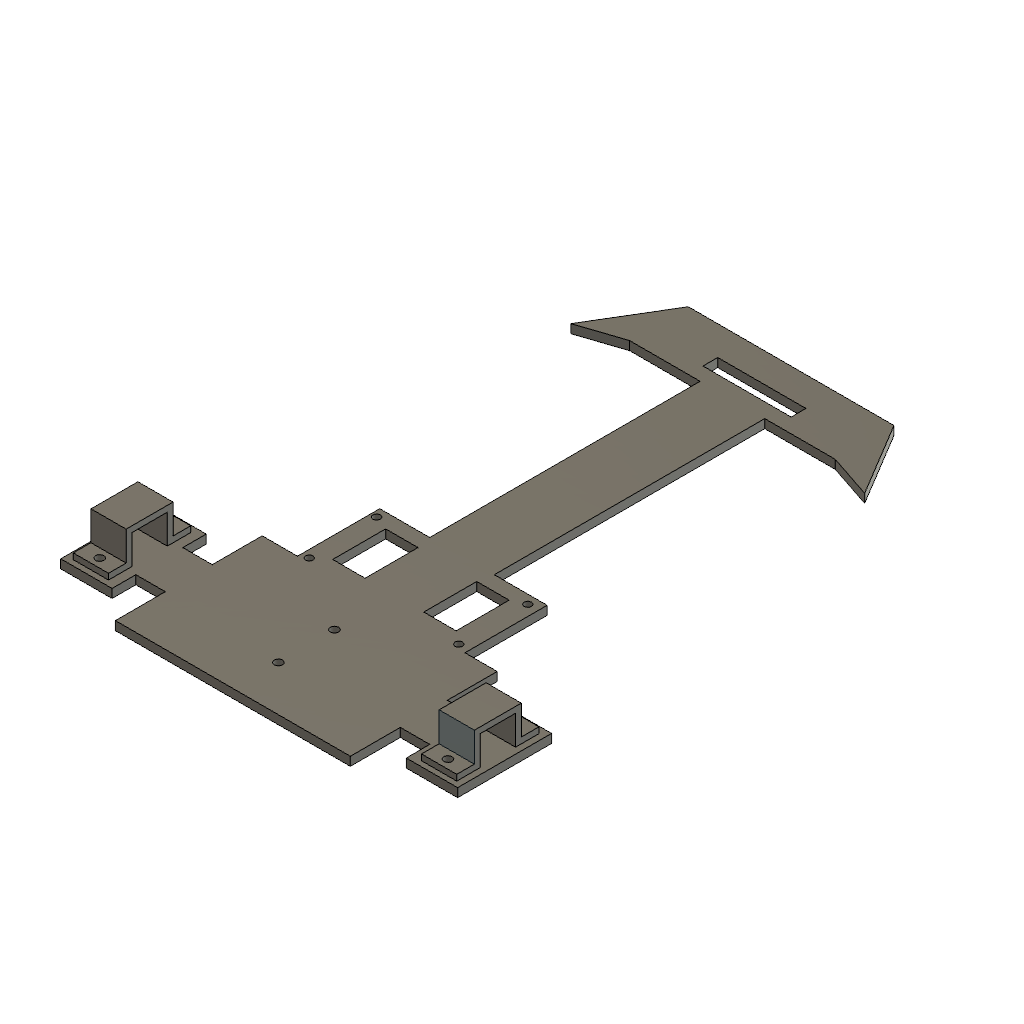
LFR (Autodesk Fusion 360 design; units mm, degrees)
part number: 2026-11-02-19-17-01-684
Autodesk Fusion 360 part; units mm, degrees
combine "Combine1" [no effect]
combine "Combine2" [no effect]
sketch "Sketch3" plane through (0, 0, 0) normal (0, 1, 0) x (1, 0, 0)
  line L0 (-67.5, 25) -> (67.5, 25)
  line L1 (67.5, 25) -> (67.5, -25)
  line L2 (67.5, -25) -> (-67.5, -25)
  line L3 (-67.5, -25) -> (-67.5, 25)
  line L4 (-10, 25) -> (10, 25)
  line L5 (10, 25) -> (10, 145)
  line L6 (10, 145) -> (-10, 145)
  line L7 (-10, 145) -> (-10, 25)
  line L8 (-35, 145) -> (35, 145)
  line L9 (35, 145) -> (35, 165)
  line L10 (35, 165) -> (-35, 165)
  line L11 (-35, 165) -> (-35, 145)
  line L12 (35, 165) -> (50, 140)
  line L13 (50, 140) -> (35, 145)
  line L14 (-35, 165) -> (-50, 140)
  line L15 (-50, 140) -> (-35, 145)
  line L16 (-15, 150) -> (15, 150)
  line L17 (15, 150) -> (15, 155)
  line L18 (15, 155) -> (-15, 155)
  line L19 (-15, 155) -> (-15, 150)
  circle A0 centre (0, 132) radius 7.5
  line L20 (-38, 20) -> (38, 20)
  line L21 (38, 20) -> (38, -20)
  line L22 (38, -20) -> (-38, -20)
  line L23 (-38, -20) -> (-38, 20)
  line L24 (-26, 53) -> (26, 53)
  line L25 (26, 53) -> (26, 25)
  line L26 (26, 25) -> (-26, 25)
  line L27 (-26, 25) -> (-26, 53)
  line L28 (-21, 30) -> (21, 30)
  line L29 (21, 30) -> (21, 48)
  line L30 (21, 48) -> (-21, 48)
  line L31 (-21, 48) -> (-21, 30)
  dimension "d11" = 135
  dimension "d12" = 50
  dimension "d13" = 20
  dimension "d14" = 120
  dimension "d15" = 70
  dimension "d16" = 20
  dimension "d17" = 15
  dimension "d18" = 76
  dimension "d19" = 40
  dimension "d20" = 52
  dimension "d21" = 28
  constraint horizontal L0
  constraint vertical L1
  constraint horizontal L2
  constraint vertical L3
  constraint horizontal L4
  constraint vertical L5
  constraint horizontal L6
  constraint vertical L7
  constraint coincident L0 L4.start
  constraint horizontal L8
  constraint vertical L9
  constraint horizontal L10
  constraint vertical L11
  constraint horizontal L16
  constraint vertical L17
  constraint horizontal L18
  constraint vertical L19
  constraint horizontal L20
  constraint vertical L21
  constraint horizontal L22
  constraint vertical L23
  constraint horizontal L24
  constraint vertical L25
  constraint horizontal L26
  constraint vertical L27
  constraint horizontal L28
  constraint vertical L29
  constraint horizontal L30
  constraint vertical L31
  measures "d11" distance of L0.start L0.end
  measures "d12" distance of L0.start L2.end
  measures "d13" distance of L4.start L4.end
  measures "d14" distance of L4.start L6.end
  measures "d15" distance of L8.start L8.end
  measures "d16" distance of L8.start L10.end
  measures "d17" diameter of A0
  measures "d18" distance of L20.start L20.end
  measures "d19" distance of L20.start L22.end
  measures "d20" distance of L24.start L24.end
  measures "d21" distance of L24.start L26.end
extrude "Extrude2" add sketch "Sketch3" along normal blind 5 contours L0 L1 L2 L3 L4 L26 | L0 L7 L24 L26 L27 L28 L30 L31 | L0 L4 L5 L7 L26 L28 | L0 L5 L24 L25 L26 L28 L29 L30 | L5 L7 L28 L30 | L5 L7 L24 L30 | L5 L6 L7 L8 L24 | L6 L8 L9 L10 L11 | L11 L14 L15 | L9 L12 L13 | L20 L21 L22 L23 makes body 1
extrude "Extrude3" cut 1 faces at (-8.6667, 5, 8.3333) along direction (0, -1, 0) blind 2 on bodies 1 bodies 1
extrude "Extrude4" add sketch "Sketch3" along normal blind 3 contours A0 bodies 1
extrude "Extrude5" add 1 faces at (26, 2, -43.6667) along direction (1, 0, 0) blind 1 on bodies 1 bodies 1
extrude "Extrude6" add 1 faces at (27, 2, -43.6667) along direction (1, 0, 0) blind 2 on bodies 1 bodies 1
extrude "Extrude7" add 1 faces at (-26, 1, -34.3333) along direction (-1, 0, 0) blind 2 on bodies 1 bodies 1
extrude "Extrude8" add 1 faces at (-10, 2, -114.3333) along direction (-1, 0, 0) blind 1 on bodies 1 bodies 1
extrude "Extrude9" add 1 faces at (10, 2, -83.6667) along direction (1, 0, 0) blind 1 on bodies 1 bodies 1
sketch "Sketch4" plane through (0, 0, 0) normal (1, 0, 0) x (0, 0, -1)
  line L0 (5, -10) -> (-7, -10)
  line L1 (-7, -10) -> (-7, -20)
  line L2 (-7, -20) -> (5, -20)
  line L3 (5, -20) -> (5, -10)
  line L4 (7, -8) -> (-9, -8)
  line L5 (-9, -8) -> (-9, -20)
  line L6 (-9, -20) -> (7, -20)
  line L7 (7, -20) -> (7, -8)
  line L8 (7, -18) -> (13, -18)
  line L9 (13, -18) -> (13, -20)
  line L10 (13, -20) -> (7, -20)
  line L11 (7, -20) -> (7, -18)
  line L12 (-9, -20) -> (-15, -20)
  line L13 (-15, -20) -> (-15, -18)
  line L14 (-15, -18) -> (-9, -18)
  line L15 (-9, -18) -> (-9, -20)
  dimension "d38" = 12
  dimension "d39" = 10
  constraint horizontal L0
  constraint vertical L1
  constraint horizontal L2
  constraint vertical L3
  constraint horizontal L4
  constraint vertical L5
  constraint horizontal L6
  constraint vertical L7
  constraint horizontal L8
  constraint vertical L9
  constraint horizontal L10
  constraint vertical L11
  constraint coincident L7 L8.start
  constraint horizontal L12
  constraint vertical L13
  constraint horizontal L14
  constraint vertical L15
  measures "d38" distance of L0.start L0.end
  measures "d39" distance of L0.start L2.end
extrude "Extrude10" add sketch "Sketch4" along normal blind 12 separate body contours L0 L1 L3 L4 L5 L6 L7 L11 L15 | L7 L8 L9 L10 L11 | L5 L12 L13 L14 L15 makes body 2
move_body "Move1" bodies 2 to x (1, 0, 0) y (0, 1, 0) z (0, 0, 1) at (-58.118, 22.9587, -0.8194)
move_body "Move2" bodies 2 to x (1, 0, 0) y (0, 1, 0) z (0, 0, 1) at (-7, 0, 0)
copy_body "CopyPasteBodies1" bodies 2 makes body 3
move_body "Move3" bodies 3 to x (1, 0, 0) y (0, 1, 0) z (0, 0, 1) at (118.5, 0, 0)
sketch "Sketch5" plane through (0, 3, 0) normal (0, 1, 0) x (-1, 0, 0)
  line L0 (21, -48) -> (10, -48)
  line L1 (10, -48) -> (10, -30)
  line L2 (10, -30) -> (21, -30)
  line L3 (21, -30) -> (21, -48)
  line L4 (-21, -30) -> (-10, -30)
  line L5 (-10, -30) -> (-10, -48)
  line L6 (-10, -48) -> (-21, -48)
  line L7 (-21, -48) -> (-21, -30)
  line L8 (15, -150) -> (15, -155)
  line L9 (15, -155) -> (-15, -155)
  line L10 (-15, -155) -> (-15, -150)
  line L11 (-15, -150) -> (15, -150)
  line L12 (-11, -145) -> (-35, -145)
  line L13 (-35, -145) -> (-50, -140)
  line L14 (-50, -140) -> (-35, -165)
  line L15 (-35, -165) -> (35, -165)
  line L16 (35, -165) -> (50, -140)
  line L17 (50, -140) -> (35, -145)
  line L18 (35, -145) -> (11, -145)
  line L19 (11, -145) -> (11, -53)
  line L20 (11, -53) -> (28, -53)
  line L21 (28, -53) -> (28, -25)
  line L22 (28, -25) -> (67.5, -25)
  line L23 (67.5, -25) -> (67.5, 25)
  line L24 (67.5, 25) -> (-67.5, 25)
  line L25 (-67.5, 25) -> (-67.5, -25)
  line L26 (-67.5, -25) -> (-29, -25)
  line L27 (-29, -25) -> (-29, -53)
  line L28 (-29, -53) -> (-11, -53)
  line L29 (-11, -53) -> (-11, -145)
  line L30 (-40, -25) -> (-67.5, -25)
  line L31 (-67.5, -25) -> (-67.5, -17)
  line L32 (-67.5, -17) -> (-40, -17)
  line L33 (-40, -17) -> (-40, -25)
  line L34 (-67.5, 25) -> (-40, 25)
  line L35 (-40, 25) -> (-40, 17.5)
  line L36 (-40, 17.5) -> (-67.5, 17.5)
  line L37 (-67.5, 17.5) -> (-67.5, 25)
  line L38 (-40, 17) -> (-67.5, 17)
  line L39 (-67.5, 17) -> (-67.5, 25)
  line L40 (-67.5, 25) -> (-40, 25)
  line L41 (-40, 25) -> (-40, 17)
  line L42 (40, 25) -> (67.5, 25)
  line L43 (67.5, 25) -> (67.5, 16.0912)
  line L44 (67.5, 16.0912) -> (40, 16.0912)
  line L45 (40, 16.0912) -> (40, 25)
  line L46 (67.5, -25) -> (40, -25)
  line L47 (40, -25) -> (40, -16)
  line L48 (40, -16) -> (67.5, -16)
  line L49 (67.5, -16) -> (67.5, -25)
  constraint horizontal L30
  constraint vertical L31
  constraint horizontal L32
  constraint vertical L33
  constraint coincident L25 L31.end
  constraint coincident L26 L30.start
  constraint horizontal L34
  constraint vertical L35
  constraint horizontal L36
  constraint vertical L37
  constraint coincident L24.end L25.start
  constraint horizontal L38
  constraint vertical L39
  constraint horizontal L40
  constraint vertical L41
  constraint horizontal L42
  constraint vertical L43
  constraint horizontal L44
  constraint vertical L45
  constraint coincident L23 L43.end
  constraint coincident L24 L42.start
  constraint horizontal L46
  constraint vertical L47
  constraint horizontal L48
  constraint vertical L49
  constraint coincident L22.end L23.start
extrude "Extrude11" cut sketch "Sketch5" against normal blind 3 contours L25 L26 L30 L31 L32 L33 | L25 L36 L38 L39 L41 | L24 L25 L34 L35 L36 L37 L39 L40 L41 | L22 L23 L46 L47 L48 L49 | L23 L24 L42 L43 L44 L45 bodies 1
sketch "Sketch6" plane through (0, 3, 0) normal (0, 1, 0) x (-1, 0, 0)
  line L0 (40, -16) -> (67.5, -16)
  line L1 (67.5, -16) -> (67.5, 16.0912)
  line L2 (67.5, 16.0912) -> (40, 16.0912)
  line L3 (40, 16.0912) -> (40, 25)
  line L4 (40, 25) -> (-40, 25)
  line L5 (-40, 25) -> (-40, 17)
  line L6 (-40, 17) -> (-67.5, 17)
  line L7 (-67.5, 17) -> (-67.5, -17)
  line L8 (-67.5, -17) -> (-40, -17)
  line L9 (-40, -17) -> (-40, -25)
  line L10 (-40, -25) -> (-29, -25)
  line L11 (-29, -25) -> (-29, -53)
  line L12 (-29, -53) -> (-11, -53)
  line L13 (-11, -53) -> (-11, -145)
  line L14 (-11, -145) -> (-35, -145)
  line L15 (-35, -145) -> (-50, -140)
  line L16 (-50, -140) -> (-35, -165)
  line L17 (-35, -165) -> (35, -165)
  line L18 (35, -165) -> (50, -140)
  line L19 (50, -140) -> (35, -145)
  line L20 (35, -145) -> (11, -145)
  line L21 (11, -145) -> (11, -53)
  line L22 (11, -53) -> (28, -53)
  line L23 (28, -53) -> (28, -25)
  line L24 (28, -25) -> (40, -25)
  line L25 (40, -25) -> (40, -16)
  line L26 (21, -48) -> (10, -48)
  line L27 (10, -48) -> (10, -30)
  line L28 (10, -30) -> (21, -30)
  line L29 (21, -30) -> (21, -48)
  line L30 (-21, -30) -> (-10, -30)
  line L31 (-10, -30) -> (-10, -48)
  line L32 (-10, -48) -> (-21, -48)
  line L33 (-21, -48) -> (-21, -30)
  line L34 (15, -150) -> (15, -155)
  line L35 (15, -155) -> (-15, -155)
  line L36 (-15, -155) -> (-15, -150)
  line L37 (-15, -150) -> (15, -150)
  line L38 (50, 8) -> (40, 8)
  line L39 (40, 8) -> (40, 16.0912)
  line L40 (40, 16.0912) -> (50, 16.0912)
  line L41 (50, 16.0912) -> (50, 8)
  line L42 (50, -8) -> (40, -8)
  line L43 (40, -8) -> (40, -16)
  line L44 (40, -16) -> (50, -16)
  line L45 (50, -16) -> (50, -8)
  line L46 (-50, -17) -> (-40, -17)
  line L47 (-40, -17) -> (-40, -8)
  line L48 (-40, -8) -> (-50, -8)
  line L49 (-50, -8) -> (-50, -17)
  line L50 (-40, 17) -> (-50, 17)
  line L51 (-50, 17) -> (-50, 8)
  line L52 (-50, 8) -> (-40, 8)
  line L53 (-40, 8) -> (-40, 17)
  constraint horizontal L38
  constraint vertical L39
  constraint horizontal L40
  constraint vertical L41
  constraint coincident L2.end L3.start
  constraint horizontal L42
  constraint vertical L43
  constraint horizontal L44
  constraint vertical L45
  constraint coincident L0.start L25.end
  constraint horizontal L46
  constraint vertical L47
  constraint horizontal L48
  constraint vertical L49
  constraint coincident L8 L46.start
  constraint horizontal L50
  constraint vertical L51
  constraint horizontal L52
  constraint vertical L53
  constraint coincident L5.end L6.start
extrude "Extrude12" cut sketch "Sketch6" against normal blind 3 contours L0 L42 L43 L44 L45 | L2 L38 L39 L40 L41 | L6 L50 L51 L52 L53 | L8 L46 L47 L48 L49 bodies 1
sketch "Sketch7" plane through (0, 3, 0) normal (0, 1, 0) x (-1, 0, 0)
  line L0 (15, -150) -> (15, -155)
  line L1 (15, -155) -> (-15, -155)
  line L2 (-15, -155) -> (-15, -150)
  line L3 (-15, -150) -> (15, -150)
  line L4 (-21, -30) -> (-10, -30)
  line L5 (-10, -30) -> (-10, -48)
  line L6 (-10, -48) -> (-21, -48)
  line L7 (-21, -48) -> (-21, -30)
  line L8 (21, -48) -> (10, -48)
  line L9 (10, -48) -> (10, -30)
  line L10 (10, -30) -> (21, -30)
  line L11 (21, -30) -> (21, -48)
  line L12 (-50, -17) -> (-50, -8)
  line L13 (-50, -8) -> (-40, -8)
  line L14 (-40, -8) -> (-40, -25)
  line L15 (-40, -25) -> (-29, -25)
  line L16 (-29, -25) -> (-29, -53)
  line L17 (-29, -53) -> (-11, -53)
  line L18 (-11, -53) -> (-11, -145)
  line L19 (-11, -145) -> (-35, -145)
  line L20 (-35, -145) -> (-50, -140)
  line L21 (-50, -140) -> (-35, -165)
  line L22 (-35, -165) -> (35, -165)
  line L23 (35, -165) -> (50, -140)
  line L24 (50, -140) -> (35, -145)
  line L25 (35, -145) -> (11, -145)
  line L26 (11, -145) -> (11, -53)
  line L27 (11, -53) -> (28, -53)
  line L28 (28, -53) -> (28, -25)
  line L29 (28, -25) -> (40, -25)
  line L30 (40, -25) -> (40, -8)
  line L31 (40, -8) -> (50, -8)
  line L32 (50, -8) -> (50, -16)
  line L33 (50, -16) -> (67.5, -16)
  line L34 (67.5, -16) -> (67.5, 16.0912)
  line L35 (67.5, 16.0912) -> (50, 16.0912)
  line L36 (50, 16.0912) -> (50, 8)
  line L37 (50, 8) -> (40, 8)
  line L38 (40, 8) -> (40, 25)
  line L39 (40, 25) -> (-40, 25)
  line L40 (-40, 25) -> (-40, 8)
  line L41 (-40, 8) -> (-50, 8)
  line L42 (-50, 8) -> (-50, 17)
  line L43 (-50, 17) -> (-67.5, 17)
  line L44 (-67.5, 17) -> (-67.5, -17)
  line L45 (-67.5, -17) -> (-50, -17)
extrude "Extrude13" cut 1 faces at (55.8333, 1, 17) along direction (0, 0, -1) blind 1 on bodies 1 bodies 1
extrude "Extrude14" cut 1 faces at (61.6667, 2, -17) along direction (0, 0, 1) blind 1 on bodies 1 bodies 1
hole "Hole1" at (-59.118, 4.9587, -10.8194) direction (0, -1, 0) diameter 2.8 depth 6 tip angle 180 bodies 1 2
hole "Hole2" at (-59.118, 4.9587, 11.1806) direction (0, -1, 0) diameter 2.8 depth 6 tip angle 180 bodies 1 2
hole "Hole3" at (59.382, 4.9587, 11.1806) direction (0, -1, 0) diameter 2.8 depth 6 tip angle 180 bodies 1 3
hole "Hole4" at (59.382, 4.9587, -10.8194) direction (0, -1, 0) diameter 2.8 depth 6 tip angle 180 bodies 1 3
hole "Hole5" at (0.0985, 3, 9.5935) direction (0, -1, 0) diameter 2.8 depth 6 tip angle 180 bodies 1
hole "Hole6" at (-0.0138, 3, -9.6026) direction (0, -1, 0) diameter 2.8 depth 6 tip angle 180 bodies 1
hole "Hole7" at (-25.4143, 3, -26.4349) direction (0, -1, 0) diameter 2.5 depth 6 tip angle 180 bodies 1
hole "Hole8" at (25.4068, 3, -26.4828) direction (0, -1, 0) diameter 2.5 depth 6 tip angle 180 bodies 1
hole "Hole9" at (25.4057, 3, -49.9685) direction (0, -1, 0) diameter 2.5 depth 6 tip angle 180 bodies 1
hole "Hole10" at (-26.0286, 3, -49.9616) direction (0, -1, 0) diameter 2.5 depth 6 tip angle 180 bodies 1
sketch "Sketch8" plane through (0, 0, 8.1806) normal (0, 0, 1) x (1, 0, 0)
  line L0 (53.382, 14.9587) -> (53.382, 4.9587)
  line L1 (53.382, 4.9587) -> (65.382, 4.9587)
  line L2 (65.382, 4.9587) -> (65.382, 14.9587)
  line L3 (65.382, 14.9587) -> (53.382, 14.9587)
